Carcasa_v4 (Autodesk Fusion 360 design; units mm, degrees)
part number: 2026-11-08-16-02-31-527
part number: 2026-11-08-16-03-12-914
part number: 2026-11-08-16-03-47-688
part number: 2026-11-08-16-03-50-916
part number: 2026-11-08-16-04-46-221
part number: 2026-11-08-16-04-50-854
part number: 2026-11-08-17-01-50-922
part number: 2026-11-08-17-01-54-591
part number: 2026-11-15-20-32-03-363
Autodesk Fusion 360 part; units mm, degrees
(part 1 of 2)
sketch "Boceto1" plane through (0, 0, 0) normal (0, 0, 1) x (1, 0, 0) in component "Cuerpo"
  line L0 (-55, -5) -> (55, -5)
  line L1 (55, -5) -> (55, 65)
  line L2 (55, 65) -> (-55, 65)
  line L3 (-55, 65) -> (-55, -5)
extrude "Extruir1" add sketch "Boceto1" along normal blind 100 makes body 1 in component "Cuerpo"
fillet "Empalme1" radius 8 4 edges at (-55, 65, 50) (55, 65, 50) (55, -5, 50) (-55, -5, 50) on bodies 1 in component "Cuerpo"
fillet "Empalme2" radius 3 128 edges at (-52.6569, -2.6569, 100) (-55, 30, 100) (-52.6569, 62.6569, 100) (0, 65, 100) (52.6569, 62.6569, 100) (55, 30, 100) (52.6569, -2.6569, 100) (0, -5, 100) (0, -5, 100) (52.6569, -2.6569, 100) (55, 30, 100) (52.6569, 62.6569, 100) (0, 65, 100) (-52.6569, 62.6569, 100) (-55, 30, 100) (-52.6569, -2.6569, 100) (52.6569, -2.6569, 100) (0, -5, 100) (-52.6569, -2.6569, 100) (-55, 30, 100) (-52.6569, 62.6569, 100) (0, 65, 100) (52.6569, 62.6569, 100) (55, 30, 100) (55, 30, 100) (52.6569, 62.6569, 100) (0, 65, 100) (-52.6569, 62.6569, 100) (-55, 30, 100) (-52.6569, -2.6569, 100) (0, -5, 100) (52.6569, -2.6569, 100) (52.6569, 62.6569, 100) (55, 30, 100) (52.6569, -2.6569, 100) (0, -5, 100) (-52.6569, -2.6569, 100) (-55, 30, 100) (-52.6569, 62.6569, 100) (0, 65, 100) (0, 65, 100) (-52.6569, 62.6569, 100) (-55, 30, 100) (-52.6569, -2.6569, 100) (0, -5, 100) (52.6569, -2.6569, 100) (55, 30, 100) (52.6569, 62.6569, 100) (-52.6569, 62.6569, 100) (0, 65, 100) (52.6569, 62.6569, 100) (55, 30, 100) (52.6569, -2.6569, 100) (0, -5, 100) (-52.6569, -2.6569, 100) (-55, 30, 100) (-55, 30, 100) (-52.6569, -2.6569, 100) (0, -5, 100) (52.6569, -2.6569, 100) (55, 30, 100) (52.6569, 62.6569, 100) (0, 65, 100) (-52.6569, 62.6569, 100) (-52.6569, -2.6569, 0) (0, -5, 0) (52.6569, -2.6569, 0) (55, 30, 0) (52.6569, 62.6569, 0) (0, 65, 0) (-52.6569, 62.6569, 0) (-55, 30, 0) (-55, 30, 0) (-52.6569, -2.6569, 0) (0, -5, 0) (52.6569, -2.6569, 0) (55, 30, 0) (52.6569, 62.6569, 0) (0, 65, 0) (-52.6569, 62.6569, 0) (-52.6569, 62.6569, 0) (-55, 30, 0) (-52.6569, -2.6569, 0) (0, -5, 0) (52.6569, -2.6569, 0) (55, 30, 0) (52.6569, 62.6569, 0) (0, 65, 0) (0, 65, 0) (-52.6569, 62.6569, 0) (-55, 30, 0) (-52.6569, -2.6569, 0) (0, -5, 0) (52.6569, -2.6569, 0) (55, 30, 0) (52.6569, 62.6569, 0) (52.6569, 62.6569, 0) (0, 65, 0) (-52.6569, 62.6569, 0) (-55, 30, 0) (-52.6569, -2.6569, 0) (0, -5, 0) (52.6569, -2.6569, 0) (55, 30, 0) (55, 30, 0) (52.6569, 62.6569, 0) (0, 65, 0) (-52.6569, 62.6569, 0) (-55, 30, 0) (-52.6569, -2.6569, 0) (0, -5, 0) (52.6569, -2.6569, 0) (52.6569, -2.6569, 0) (55, 30, 0) (52.6569, 62.6569, 0) (0, 65, 0) (-52.6569, 62.6569, 0) (-55, 30, 0) (-52.6569, -2.6569, 0) (0, -5, 0) (0, -5, 0) (52.6569, -2.6569, 0) (55, 30, 0) (52.6569, 62.6569, 0) (0, 65, 0) (-52.6569, 62.6569, 0) (-55, 30, 0) (-52.6569, -2.6569, 0) on bodies 1 in component "Cuerpo"
ref_plane "PlanoDeObra1" through (0, -3, 0) normal (0, 1, 0) x (0, 0, 1) in component "Cuerpo"
sketch "Boceto2" plane through (0, -3, 0) normal (0, 1, 0) x (1, 0, 0) in component "Cuerpo"
  line L0 (-70, 10) -> (70, 10)
  line L1 (70, 10) -> (70, -120)
  line L2 (70, -120) -> (-70, -120)
  line L3 (-70, -120) -> (-70, 10)
extrude "Extruir2" cut sketch "Boceto2" along normal mid plane 6 bodies 1 in component "Cuerpo"
shell "Vaciado1" thickness 2.5 removed faces 1 at (17, 0, 66.6667) on bodies 1 in component "Cuerpo"
sketch "Boceto3" plane through (0, 0, 0) normal (0, 1, 0) x (1, 0, 0) in component "Cuerpo"
  circle A0 centre (-48.8, -12) radius 4
  circle A1 centre (-48.8, -88) radius 4
  circle A2 centre (48.8, -12) radius 4
  circle A3 centre (48.8, -88) radius 4
extrude "Extruir3" add sketch "Boceto3" along normal blind 12 bodies 1 in component "Cuerpo"
ref_plane "PlanoDeObra2" through (0, 0, 2) normal (0, 0, 1) x (1, 0, 0) in component "Cuerpo"
ref_plane "PlanoDeObra3" through (0, 0, 2) normal (0, 0, 1) x (1, 0, 0) in component "Cuerpo"
ref_plane "PlanoDeObra4" through (0, 0, 8) normal (0, 0, 1) x (1, 0, 0) in component "Cuerpo"
ref_plane "PlanoDeObra5" through (0, 21, 0) normal (0, 1, 0) x (0, 0, 1) in component "Cuerpo"
ref_plane "PlanoDeObra6" through (0, 21, 0) normal (0, 1, 0) x (0, 0, 1) in component "Cuerpo"
ref_plane "PlanoDeObra7" through (0, 0, 5) normal (0, 0, 1) x (1, 0, 0) in component "Cuerpo"
sketch "Boceto10" plane through (0, 0, 5) normal (0, 0, 1) x (1, 0, 0) in component "Cuerpo"
  line L0 (-20, 64) -> (20, 64)
  line L1 (20, 64) -> (20, 73)
  line L2 (20, 73) -> (-20, 73)
  line L3 (-20, 73) -> (-20, 64)
extrude "Extruir10" add sketch "Boceto10" along normal blind 90 bodies 1 in component "Cuerpo"
ref_plane "PlanoDeObra8" through (0, 0, 4) normal (0, 0, 1) x (1, 0, 0) in component "Cuerpo"
sketch "Boceto11" plane through (0, 0, 4) normal (0, 0, 1) x (1, 0, 0) in component "Cuerpo"
  line L0 (-10.3, 74) -> (10.3, 74)
  line L1 (10.3, 74) -> (14, 67)
  line L2 (14, 67) -> (-14, 67)
  line L3 (-14, 67) -> (-10.3, 74)
extrude "Extruir11" cut sketch "Boceto11" along normal blind 81 bodies 1 in component "Cuerpo"
sketch "Boceto12" plane through (0, 0, 0) normal (1, 0, 0) x (0, 0, -1) in component "Cuerpo"
  circle A0 centre (-75, 70) radius 2
extrude "Extruir12" cut sketch "Boceto12" along normal mid plane 50 bodies 1 in component "Cuerpo"
sketch "Boceto13" plane through (0, 0, 0) normal (0, 0, 1) x (1, 0, 0) in component "Cuerpo"
  circle A0 centre (-25, 30) radius 1.5
  circle A1 centre (25, 30) radius 1.5
extrude "Extruir13" cut sketch "Boceto13" along normal blind 4 bodies 1 in component "Cuerpo"
ref_plane "PlanoDeObra9" through (0, 0, 96) normal (0, 0, 1) x (1, 0, 0) in component "Cuerpo"
ref_plane "PlanoDeObra10" through (0, 0, 100) normal (0, 0, 1) x (1, 0, 0) in component "Cuerpo"
ref_plane "PlanoDeObra1" through (0, -3.5, 0) normal (0, 1, 0) x (0, 0, 1) in component "Tapa frontal"
sketch "Boceto1 (2)" plane through (0, -3.5, 0) normal (0, 1, 0) x (1, 0, 0) in component "Tapa frontal"
  line L0 (-54.4, 0) -> (54.4, 0)
  line L1 (54.4, 0) -> (54.4, -100)
  line L2 (54.4, -100) -> (-54.4, -100)
  line L3 (-54.4, -100) -> (-54.4, 0)
extrude "Extruir1'" add sketch "Boceto1 (2)" along normal mid plane 3 separate body makes body 2 in component "Tapa frontal"
fillet "Empalme1'" radius 3 4 edges at (-54.4, -3.5, 100) (-54.4, -3.5, 0) (54.4, -3.5, 0) (54.4, -3.5, 100) on bodies 2 in component "Tapa frontal"
fillet "Empalme2'" radius 1.5 64 edges at (53.5213, -5, 99.1213) (54.4, -5, 50) (53.5213, -5, 0.8787) (0, -5, 0) (-53.5213, -5, 0.8787) (-54.4, -5, 50) (-53.5213, -5, 99.1213) (0, -5, 100) (54.4, -5, 50) (53.5213, -5, 99.1213) (0, -5, 100) (-53.5213, -5, 99.1213) (-54.4, -5, 50) (-53.5213, -5, 0.8787) (0, -5, 0) (53.5213, -5, 0.8787) (0, -5, 100) (-53.5213, -5, 99.1213) (-54.4, -5, 50) (-53.5213, -5, 0.8787) (0, -5, 0) (53.5213, -5, 0.8787) (54.4, -5, 50) (53.5213, -5, 99.1213) (-53.5213, -5, 99.1213) (0, -5, 100) (53.5213, -5, 99.1213) (54.4, -5, 50) (53.5213, -5, 0.8787) (0, -5, 0) (-53.5213, -5, 0.8787) (-54.4, -5, 50) (-54.4, -5, 50) (-53.5213, -5, 0.8787) (0, -5, 0) (53.5213, -5, 0.8787) (54.4, -5, 50) (53.5213, -5, 99.1213) (0, -5, 100) (-53.5213, -5, 99.1213) (-53.5213, -5, 0.8787) (-54.4, -5, 50) (-53.5213, -5, 99.1213) (0, -5, 100) (53.5213, -5, 99.1213) (54.4, -5, 50) (53.5213, -5, 0.8787) (0, -5, 0) (0, -5, 0) (53.5213, -5, 0.8787) (54.4, -5, 50) (53.5213, -5, 99.1213) (0, -5, 100) (-53.5213, -5, 99.1213) (-54.4, -5, 50) (-53.5213, -5, 0.8787) (53.5213, -5, 0.8787) (0, -5, 0) (-53.5213, -5, 0.8787) (-54.4, -5, 50) (-53.5213, -5, 99.1213) (0, -5, 100) (53.5213, -5, 99.1213) (54.4, -5, 50) on bodies 2 in component "Tapa frontal"
ref_plane "PlanoDeObra2" through (0, 1.5, 0) normal (0, 1, 0) x (0, 0, 1) in component "Tapa frontal"
sketch "Boceto2 (2)" plane through (0, 1.5, 0) normal (0, 1, 0) x (1, 0, 0) in component "Tapa frontal"
  line L0 (-51.6, -2.8) -> (51.6, -2.8)
  line L1 (51.6, -2.8) -> (51.6, -97.2)
  line L2 (51.6, -97.2) -> (-51.6, -97.2)
  line L3 (-51.6, -97.2) -> (-51.6, -2.8)
  line L4 (-50, -4.4) -> (50, -4.4)
  line L5 (50, -4.4) -> (50, -95.6)
  line L6 (50, -95.6) -> (-50, -95.6)
  line L7 (-50, -95.6) -> (-50, -4.4)
extrude "Extruir2'" add sketch "Boceto2 (2)" along normal mid plane 7 bodies 2 in component "Tapa frontal"
ref_plane "PlanoDeObra3" through (0, 1.5, 0) normal (0, 1, 0) x (0, 0, 1) in component "Tapa frontal"
sketch "Boceto3 (2)" plane through (0, 1.5, 0) normal (0, 1, 0) x (1, 0, 0) in component "Tapa frontal"
  line L0 (-53.8, -7) -> (-43.8, -7)
  line L1 (-43.8, -7) -> (-43.8, -17)
  line L2 (-43.8, -17) -> (-53.8, -17)
  line L3 (-53.8, -17) -> (-53.8, -7)
  line L4 (-53.8, -83) -> (-43.8, -83)
  line L5 (-43.8, -83) -> (-43.8, -93)
  line L6 (-43.8, -93) -> (-53.8, -93)
  line L7 (-53.8, -93) -> (-53.8, -83)
  line L8 (43.8, -7) -> (53.8, -7)
  line L9 (53.8, -7) -> (53.8, -17)
  line L10 (53.8, -17) -> (43.8, -17)
  line L11 (43.8, -17) -> (43.8, -7)
  line L12 (43.8, -83) -> (53.8, -83)
  line L13 (53.8, -83) -> (53.8, -93)
  line L14 (53.8, -93) -> (43.8, -93)
  line L15 (43.8, -93) -> (43.8, -83)
extrude "Extruir3'" cut sketch "Boceto3 (2)" along normal mid plane 7 bodies 2 in component "Tapa frontal"
ref_plane "PlanoDeObra4" through (0, -1.25, 0) normal (0, 1, 0) x (0, 0, 1) in component "Tapa frontal"
sketch "Boceto4" plane through (0, -1.25, 0) normal (0, 1, 0) x (1, 0, 0) in component "Tapa frontal"
  circle A0 centre (-48.8, -12) radius 4
  circle A1 centre (-48.8, -88) radius 4
  circle A2 centre (48.8, -12) radius 4
  circle A3 centre (48.8, -88) radius 4
extrude "Extruir4" add sketch "Boceto4" along normal mid plane 1.5 bodies 2 in component "Tapa frontal"
ref_plane "PlanoDeObra5" through (0, -3.5, 0) normal (0, 1, 0) x (0, 0, 1) in component "Tapa frontal"
sketch "Boceto5" plane through (0, -3.5, 0) normal (0, 1, 0) x (1, 0, 0) in component "Tapa frontal"
  circle A0 centre (-48.8, -12) radius 1.7
  circle A1 centre (-48.8, -88) radius 1.7
  circle A2 centre (48.8, -12) radius 1.7
  circle A3 centre (48.8, -88) radius 1.7
extrude "Extruir5" cut sketch "Boceto5" along normal mid plane 10 bodies 2 in component "Tapa frontal"
ref_plane "PlanoDeObra6" through (0, -5, 0) normal (0, 1, 0) x (0, 0, 1) in component "Tapa frontal"
sketch "Boceto6" plane through (0, -5, 0) normal (0, 1, 0) x (1, 0, 0) in component "Tapa frontal"
  circle A0 centre (-48.8, -12) radius 3.25
  circle A1 centre (-48.8, -88) radius 3.25
  circle A2 centre (48.8, -12) radius 3.25
  circle A3 centre (48.8, -88) radius 3.25
extrude "Extruir6" cut sketch "Boceto6" along normal blind 1.5 bodies 2 in component "Tapa frontal"
ref_plane "PlanoDeObra7" through (0, 2.25, 0) normal (0, 1, 0) x (0, 0, 1) in component "Tapa frontal"
ref_plane "PlanoDeObra8" through (0, 2.25, 0) normal (0, 1, 0) x (0, 0, 1) in component "Tapa frontal"
ref_plane "PlanoDeObra9" through (0, -5.75, 0) normal (0, 1, 0) x (0, 0, 1) in component "Tapa frontal"
sketch "Boceto9" plane through (0, -5.75, 0) normal (0, 1, 0) x (1, 0, 0) in component "Tapa frontal"
  line L0 (-12, -52) -> (12, -52)
  line L1 (12, -52) -> (12, -95)
  line L2 (12, -95) -> (-12, -95)
  line L3 (-12, -95) -> (-12, -52)
extrude "Extruir9" add sketch "Boceto9" along normal mid plane 1.5 separate body makes body 3 in component "Tapa frontal"
fillet "Empalme3" radius 3 4 edges at (-12, -5.75, 95) (-12, -5.75, 52) (12, -5.75, 52) (12, -5.75, 95) on bodies 3 in component "Tapa frontal"
ref_plane "PlanoDeObra10" through (0, -12.45, 0) normal (0, 1, 0) x (0, 0, 1) in component "Tapa frontal"
sketch "Boceto10 (2)" plane through (0, -12.45, 0) normal (0, 1, 0) x (1, 0, 0) in component "Tapa frontal"
  arc A0 (-6.5, -60.4) -> (6.5, -60.4) centre (0, -60.4) ccw
  arc A1 (-5, -60.4) -> (5, -60.4) centre (0, -60.4) ccw
  line L0 (6.5, -60.4) -> (5, -60.4)
  line L1 (-6.5, -60.4) -> (-5, -60.4)
  arc A2 (-6.5, -72.4) -> (6.5, -72.4) centre (0, -72.4) ccw
  arc A3 (-5, -72.4) -> (5, -72.4) centre (0, -72.4) ccw
  line L2 (6.5, -72.4) -> (5, -72.4)
  line L3 (-6.5, -72.4) -> (-5, -72.4)
  arc A4 (-6.5, -84.3) -> (6.5, -84.3) centre (0, -84.3) ccw
  arc A5 (-5, -84.3) -> (5, -84.3) centre (0, -84.3) ccw
  line L4 (6.5, -84.3) -> (5, -84.3)
  line L5 (-6.5, -84.3) -> (-5, -84.3)
extrude "Extruir10'" add sketch "Boceto10 (2)" along normal mid plane 12.1 bodies 3 in component "Tapa frontal"
ref_plane "PlanoDeObra11" through (0, -3.5, 0) normal (0, 1, 0) x (0, 0, 1) in component "Tapa frontal"
sketch "Boceto11 (2)" plane through (0, -3.5, 0) normal (0, 1, 0) x (1, 0, 0) in component "Tapa frontal"
  circle A0 centre (0, -60.4) radius 3.8
  circle A1 centre (0, -72.4) radius 3.8
  circle A2 centre (0, -84.3) radius 3.8
extrude "Extruir11'" cut sketch "Boceto11 (2)" along normal mid plane 10 bodies 2 3 in component "Tapa frontal"
ref_plane "PlanoDeObra12" through (0, -3.5, 0) normal (0, 1, 0) x (0, 0, 1) in component "Tapa frontal"
ref_plane "PlanoDeObra1" through (0, -1, 0) normal (0, 1, 0) x (0, 0, 1) in component "Junta TPU"
sketch "Boceto1 (3)" plane through (0, -1, 0) normal (0, 1, 0) x (1, 0, 0) in component "Junta TPU"
  line L0 (-54.4, 0) -> (54.4, 0)
  line L1 (54.4, 0) -> (54.4, -100)
  line L2 (54.4, -100) -> (-54.4, -100)
  line L3 (-54.4, -100) -> (-54.4, 0)
  line L4 (-51.9, -2.5) -> (51.9, -2.5)
  line L5 (51.9, -2.5) -> (51.9, -97.5)
  line L6 (51.9, -97.5) -> (-51.9, -97.5)
  line L7 (-51.9, -97.5) -> (-51.9, -2.5)
extrude "Extruir1''" add sketch "Boceto1 (3)" along normal mid plane 2 separate body makes body 4 in component "Junta TPU"
fillet "Empalme1''" radius 3 4 edges at (-54.4, -1, 100) (-54.4, -1, 0) (54.4, -1, 0) (54.4, -1, 100) on bodies 4 in component "Junta TPU"
ref_plane "PlanoDeObra2" through (0, -1, 0) normal (0, 1, 0) x (0, 0, 1) in component "Junta TPU"
sketch "Boceto2 (3)" plane through (0, -1, 0) normal (0, 1, 0) x (1, 0, 0) in component "Junta TPU"
  circle A0 centre (-48.8, -12) radius 4.3
  circle A1 centre (-48.8, -88) radius 4.3
  circle A2 centre (48.8, -12) radius 4.3
  circle A3 centre (48.8, -88) radius 4.3
extrude "Extruir2''" cut sketch "Boceto2 (3)" along normal mid plane 3 bodies 4 in component "Junta TPU"
sketch "Boceto1 (4)" plane through (0, 0, 0) normal (0, 0, 1) x (1, 0, 0) in component "Techo solar"
  point P0 (-57.5, -24)
  point P1 (57.5, -24)
  point P2 (0, 82.1853)
ref_plane "PlanoDeObra1" through (-57.5, -24, 104) normal (0, -0.34202, 0.939693) x (1, 0, 0) in component "Techo solar"
ref_plane "PlanoDeObra2" through (-57.5, -25.3681, 107.7588) normal (0, -0.34202, 0.939693) x (1, 0, 0) in component "Techo solar"
sketch "Boceto2 (4)" plane through (0, -36.2324, 99.5478) normal (0, -0.34202, 0.939693) x (1, 0, 0) in component "Techo solar"
  line L0 (-57.5, 13.0175) -> (57.5, 13.0175)
  line L1 (57.5, 13.0175) -> (57.5, 126.0175)
  line L2 (57.5, 126.0175) -> (-57.5, 126.0175)
  line L3 (-57.5, 126.0175) -> (-57.5, 13.0175)
extrude "Extruir1'''" add sketch "Boceto2 (4)" along normal blind 4 separate body makes body 5 in component "Techo solar"
ref_plane "PlanoDeObra3" through (0, 0, 118) normal (0, 0, 1) x (1, 0, 0) in component "Techo solar"
sketch "Boceto3 (3)" plane through (0, 0, 118) normal (0, 0, 1) x (1, 0, 0) in component "Techo solar"
  line L0 (28, 22) -> (56, 22)
  line L1 (56, 22) -> (56, 80)
  line L2 (56, 80) -> (28, 80)
  line L3 (28, 80) -> (28, 22)
extrude "Extruir2'''" add sketch "Boceto3 (3)" along normal blind 32 bodies 5 in component "Techo solar"
fillet "Empalme1'''" radius 3 8 edges at (28, 22, 119.3713) (56, 22, 119.3713) (28, 80, 129.9265) (56, 80, 129.9265) (56, 80, 148.0548) (56, 22, 137.4997) (28, 80, 148.0548) (28, 22, 137.4997) on bodies 5 in component "Techo solar"
sketch "Boceto4 (2)" plane through (0, -36.2324, 99.5478) normal (0, -0.34202, 0.939693) x (1, 0, 0) in component "Techo solar"
  line L0 (26, 53.0175) -> (58, 53.0175)
  line L1 (58, 53.0175) -> (58, 131.0175)
  line L2 (58, 131.0175) -> (26, 131.0175)
  line L3 (26, 131.0175) -> (26, 53.0175)
extrude "Extruir3''" cut sketch "Boceto4 (2)" against normal blind 40 bodies 5 in component "Techo solar"
ref_plane "PlanoDeObra4" through (0, 0, 100) normal (0, 0, 1) x (1, 0, 0) in component "Techo solar"
ref_plane "PlanoDeObra5" through (0, 0, 100) normal (0, 0, 1) x (1, 0, 0) in component "Techo solar"
ref_plane "PlanoDeObra6" through (0, 0, 100) normal (0, 0, 1) x (1, 0, 0) in component "Techo solar"
ref_plane "PlanoDeObra7" through (0, 0, 100) normal (0, 0, 1) x (1, 0, 0) in component "Techo solar"
ref_plane "PlanoDeObra8" through (0, 0, 100) normal (0, 0, 1) x (1, 0, 0) in component "Techo solar"
ref_plane "PlanoDeObra9" through (0, 0, 150) normal (0, 0, 1) x (1, 0, 0) in component "Techo solar"
sketch "Boceto10 (3)" plane through (0, 0, 150) normal (0, 0, 1) x (1, 0, 0) in component "Techo solar"
  line L0 (30, 24) -> (54, 24)
  line L1 (54, 24) -> (54, 78)
  line L2 (54, 78) -> (30, 78)
  line L3 (30, 78) -> (30, 24)
extrude "Extruir9'" cut sketch "Boceto10 (3)" along normal up to surface end surface through (-57.5, -25.3681, 107.7588) normal (0, -0.34202, 0.939693) offset 0 bodies 5 in component "Techo solar"
sketch "Boceto11 (3)" plane through (0, -37.6005, 103.3065) normal (0, -0.34202, 0.939693) x (1, 0, 0) in component "Techo solar"
  line L0 (-55, 17.7175) -> (25.6, 17.7175)
  line L1 (25.6, 17.7175) -> (25.6, 118.3175)
  line L2 (25.6, 118.3175) -> (-55, 118.3175)
  line L3 (-55, 118.3175) -> (-55, 17.7175)
extrude "Extruir10''" cut sketch "Boceto11 (3)" against normal blind 2.6 bodies 5 in component "Techo solar"
sketch "Boceto12 (2)" plane through (0, -37.6005, 103.3065) normal (0, -0.34202, 0.939693) x (1, 0, 0) in component "Techo solar"
  line L0 (-48, 19.7175) -> (23.6, 19.7175)
  line L1 (23.6, 19.7175) -> (23.6, 116.3175)
  line L2 (23.6, 116.3175) -> (-48, 116.3175)
  line L3 (-48, 116.3175) -> (-48, 19.7175)
  line L4 (-55, 108.0175) -> (-48.2, 108.0175)
  line L5 (-48.2, 108.0175) -> (-48.2, 116.3175)
  line L6 (-48.2, 116.3175) -> (-55, 116.3175)
  line L7 (-55, 116.3175) -> (-55, 108.0175)
extrude "Extruir11''" cut sketch "Boceto12 (2)" against normal blind 4.6 bodies 5 in component "Techo solar"
sketch "Boceto13 (2)" plane through (0, -37.6005, 103.3065) normal (0, -0.34202, 0.939693) x (1, 0, 0) in component "Techo solar"
  line L0 (-40, 15.7175) -> (-30, 15.7175)
  line L1 (-30, 15.7175) -> (-30, 19.3175)
  line L2 (-30, 19.3175) -> (-40, 19.3175)
  line L3 (-40, 19.3175) -> (-40, 15.7175)
  line L4 (-40, 116.7175) -> (-30, 116.7175)
  line L5 (-30, 116.7175) -> (-30, 120.3175)
  line L6 (-30, 120.3175) -> (-40, 120.3175)
  line L7 (-40, 120.3175) -> (-40, 116.7175)
  line L8 (0, 15.7175) -> (10, 15.7175)
  line L9 (10, 15.7175) -> (10, 19.3175)
  line L10 (10, 19.3175) -> (0, 19.3175)
  line L11 (0, 19.3175) -> (0, 15.7175)
  line L12 (0, 116.7175) -> (10, 116.7175)
  line L13 (10, 116.7175) -> (10, 120.3175)
  line L14 (10, 120.3175) -> (0, 120.3175)
  line L15 (0, 120.3175) -> (0, 116.7175)
extrude "Extruir12'" add sketch "Boceto13 (2)" along normal blind 1.2 bodies 5 in component "Techo solar"
ref_plane "PlanoDeObra10" through (0, 0, 122) normal (0, 0, 1) x (1, 0, 0) in component "Techo solar"
ref_plane "PlanoDeObra1" through (0, 0, 150) normal (0, 0, 1) x (1, 0, 0) in component "Tapa sensor"
sketch "Boceto1 (5)" plane through (0, 0, 150) normal (0, 0, 1) x (1, 0, 0) in component "Tapa sensor"
  line L0 (28, 22) -> (56, 22)
  line L1 (56, 22) -> (56, 80)
  line L2 (56, 80) -> (28, 80)
  line L3 (28, 80) -> (28, 22)
extrude "Extruir1''''" add sketch "Boceto1 (5)" along normal blind 3 separate body makes body 6 in component "Tapa sensor"
fillet "Empalme1''''" radius 3 4 edges at (28, 80, 151.5) (56, 80, 151.5) (56, 22, 151.5) (28, 22, 151.5) on bodies 6 in component "Tapa sensor"
ref_plane "PlanoDeObra2" through (0, 0, 150) normal (0, 0, 1) x (1, 0, 0) in component "Tapa sensor"
sketch "Boceto2 (5)" plane through (0, 0, 150) normal (0, 0, 1) x (1, 0, 0) in component "Tapa sensor"
  line L0 (30.2, 24.2) -> (53.8, 24.2)
  line L1 (53.8, 24.2) -> (53.8, 77.8)
  line L2 (53.8, 77.8) -> (30.2, 77.8)
  line L3 (30.2, 77.8) -> (30.2, 24.2)
  line L4 (31.7, 25.7) -> (52.3, 25.7)
  line L5 (52.3, 25.7) -> (52.3, 76.3)
  line L6 (52.3, 76.3) -> (31.7, 76.3)
  line L7 (31.7, 76.3) -> (31.7, 25.7)
extrude "Extruir2''''" add sketch "Boceto2 (5)" against normal blind 2.5 bodies 6 in component "Tapa sensor"
ref_plane "PlanoDeObra3" through (0, 0, 147) normal (0, 0, 1) x (1, 0, 0) in component "Tapa sensor"
sketch "Boceto3 (4)" plane through (0, 0, 147) normal (0, 0, 1) x (1, 0, 0) in component "Tapa sensor"
  line L0 (29, 74) -> (55, 74)
  line L1 (55, 74) -> (55, 79)
  line L2 (55, 79) -> (29, 79)
  line L3 (29, 79) -> (29, 74)
extrude "Extruir3'''" cut sketch "Boceto3 (4)" along normal blind 3 bodies 6 in component "Tapa sensor"
ref_plane "PlanoDeObra4" through (0, 0, 150) normal (0, 0, 1) x (1, 0, 0) in component "Tapa sensor"
ref_plane "PlanoDeObra5" through (0, 0, 151) normal (0, 0, 1) x (1, 0, 0) in component "Tapa sensor"
ref_plane "PlanoDeObra6" through (0, 0, 153) normal (0, 0, 1) x (1, 0, 0) in component "Tapa sensor"
sketch "Boceto6 (2)" plane through (0, 0, 153) normal (0, 0, 1) x (1, 0, 0) in component "Tapa sensor"
  circle A0 centre (42, 31) radius 9
  circle A1 centre (42, 31) radius 7.9
extrude "Extruir6'" add sketch "Boceto6 (2)" along normal blind 1.5 bodies 6 in component "Tapa sensor"
ref_plane "PlanoDeObra7" through (42, 0, 0) normal (1, 0, 0) x (0, 1, 0) in component "Tapa sensor"
sketch "Boceto7" plane through (42, 0, 0) normal (1, 0, 0) x (0, 0, -1) in component "Tapa sensor"
  line L0 (-149.5, 31) -> (-149.5, 33.5)
  line L1 (-149.5, 33.5) -> (-150, 33.5)
  line L2 (-150, 33.5) -> (-153, 38.7)
  line L3 (-153, 38.7) -> (-153.6, 38.7)
  line L4 (-153.6, 38.7) -> (-153.6, 31)
  line L5 (-153.6, 31) -> (-149.5, 31)
revolve "Revolución1" cut sketch "Boceto7" angle 360 about axis through (42, 31, 153.6) along (0, 0, -1) bodies 6 in component "Tapa sensor"
ref_plane "PlanoDeObra11" through (0, 0, 122) normal (0, 0, 1) x (1, 0, 0) in component "Techo solar"
sketch "Boceto1 (6)" plane through (0, 0, 0) normal (0, 0, 1) x (1, 0, 0) in component "Soporte pared"
  line L0 (-35, 73.3) -> (35, 73.3)
  line L1 (35, 73.3) -> (35, 86)
  line L2 (35, 86) -> (-35, 86)
  line L3 (-35, 86) -> (-35, 73.3)
extrude "Extruir1'''''" add sketch "Boceto1 (6)" along normal blind 95 separate body makes body 7 in component "Soporte pared"
fillet "Empalme1'''''" radius 5 4 edges at (35, 79.65, 0) (35, 79.65, 95) (-35, 79.65, 0) (-35, 79.65, 95) on bodies 7 in component "Soporte pared"
ref_plane "PlanoDeObra1" through (0, 0, 8) normal (0, 0, 1) x (1, 0, 0) in component "Soporte pared"
sketch "Boceto2 (6)" plane through (0, 0, 8) normal (0, 0, 1) x (1, 0, 0) in component "Soporte pared"
  line L0 (-13.54, 67.3) -> (13.54, 67.3)
  line L1 (13.54, 67.3) -> (10.21, 73.6)
  line L2 (10.21, 73.6) -> (-10.21, 73.6)
  line L3 (-10.21, 73.6) -> (-13.54, 67.3)
extrude "Extruir2'''''" add sketch "Boceto2 (6)" along normal blind 76.7 bodies 7 in component "Soporte pared"
ref_plane "PlanoDeObra2" through (0, 82.15, 0) normal (0, 1, 0) x (0, 0, 1) in component "Soporte pared"
sketch "Boceto3 (5)" plane through (0, 82.15, 0) normal (0, 1, 0) x (1, 0, 0) in component "Soporte pared"
  line L0 (-29, -8) -> (29, -8)
  line L1 (29, -8) -> (29, -87)
  line L2 (29, -87) -> (-29, -87)
  line L3 (-29, -87) -> (-29, -8)
extrude "Extruir3''''" cut sketch "Boceto3 (5)" along normal mid plane 7.8 bodies 7 in component "Soporte pared"
ref_plane "PlanoDeObra3" through (0, 80, 0) normal (0, 1, 0) x (0, 0, 1) in component "Soporte pared"
sketch "Boceto4 (3)" plane through (0, 80, 0) normal (0, 1, 0) x (1, 0, 0) in component "Soporte pared"
  circle A0 centre (-26, -14) radius 2.5
  circle A1 centre (-26, -81) radius 2.5
  circle A2 centre (26, -14) radius 2.5
  circle A3 centre (26, -81) radius 2.5
extrude "Extruir4'" cut sketch "Boceto4 (3)" along normal mid plane 20 bodies 7 in component "Soporte pared"
ref_plane "PlanoDeObra4" through (0, 73.3, 0) normal (0, 1, 0) x (0, 0, 1) in component "Soporte pared"
sketch "Boceto5 (2)" plane through (0, 73.3, 0) normal (0, 1, 0) x (1, 0, 0) in component "Soporte pared"
  circle A0 centre (-26, -14) radius 4.5
  circle A1 centre (-26, -81) radius 4.5
  circle A2 centre (26, -14) radius 4.5
  circle A3 centre (26, -81) radius 4.5
extrude "Extruir5'" cut sketch "Boceto5 (2)" along normal blind 2.5 bodies 7 in component "Soporte pared"
sketch "Boceto6 (3)" plane through (0, 0, 0) normal (1, 0, 0) x (0, 0, -1) in component "Soporte pared"
  circle A0 centre (-75, 70) radius 2
extrude "Extruir6''" cut sketch "Boceto6 (3)" along normal mid plane 60 bodies 7 in component "Soporte pared"
ref_plane "PlanoDeObra1" through (0, 96, 0) normal (0, 1, 0) x (0, 0, 1) in component "Pared (referencia)"
sketch "Boceto1 (7)" plane through (0, 96, 0) normal (0, 1, 0) x (1, 0, 0) in component "Pared (referencia)"
  line L0 (-120, 80) -> (120, 80)
  line L1 (120, 80) -> (120, -240)
  line L2 (120, -240) -> (-120, -240)
  line L3 (-120, -240) -> (-120, 80)
extrude "Extruir1''''''" add sketch "Boceto1 (7)" along normal mid plane 20 separate body makes body 8 in component "Pared (referencia)"
ref_plane "PlanoDeObra1" through (0, 54, 0) normal (0, 1, 0) x (0, 0, 1) in component "Traba bateria"
sketch "Boceto1 (8)" plane through (0, 54, 0) normal (0, 1, 0) x (1, 0, 0) in component "Traba bateria"
  line L0 (-22.5, -45.5) -> (-15.5, -45.5)
  line L1 (-15.5, -45.5) -> (-15.5, -96.5)
  line L2 (-15.5, -96.5) -> (-22.5, -96.5)
  line L3 (-22.5, -96.5) -> (-22.5, -45.5)
extrude "Traba bateria (1)" add sketch "Boceto1 (8)" along normal blind 2 separate body makes body 9 in component "Traba bateria"
ref_plane "PlanoDeObra2" through (0, 53, 0) normal (0, 1, 0) x (0, 0, 1) in component "Traba bateria"
sketch "Boceto2 (7)" plane through (0, 53, 0) normal (0, 1, 0) x (1, 0, 0) in component "Traba bateria"
  circle A0 centre (-19, -49.5) radius 1.7
  circle A1 centre (-19, -92.5) radius 1.7
extrude "Agujeros traba M3 (1)" cut sketch "Boceto2 (7)" along normal blind 4 bodies 9 in component "Traba bateria"
ref_plane "PlanoDeObra11" through (0, 0, 0) normal (0, 1, 0) x (0, 0, 1) in component "Cuerpo"
sketch "Boceto16" plane through (0, 0, 0) normal (0, 1, 0) x (1, 0, 0) in component "Cuerpo"
  circle A0 centre (-48.8, -12) radius 4.5
  circle A1 centre (-48.8, -88) radius 4.5
  circle A2 centre (48.8, -12) radius 4.5
  circle A3 centre (48.8, -88) radius 4.5
extrude "Torretas tapa d9 (1)" add sketch "Boceto16" along normal blind 12 bodies 1 in component "Cuerpo"
ref_plane "PlanoDeObra12" through (0, 0, 0) normal (0, 1, 0) x (0, 0, 1) in component "Cuerpo"
sketch "Boceto17" plane through (0, 0, 0) normal (0, 1, 0) x (1, 0, 0) in component "Cuerpo"
  circle A0 centre (-48.8, -12) radius 2.5
  circle A1 centre (-48.8, -88) radius 2.5
  circle A2 centre (48.8, -12) radius 2.5
  circle A3 centre (48.8, -88) radius 2.5
extrude "Insertos tapa (inserto 5x4) (1)" cut sketch "Boceto17" along normal blind 5 bodies 1 in component "Cuerpo"
ref_plane "PlanoDeObra13" through (0, 5, 0) normal (0, 1, 0) x (0, 0, 1) in component "Cuerpo"
sketch "Boceto18" plane through (0, 5, 0) normal (0, 1, 0) x (1, 0, 0) in component "Cuerpo"
  circle A0 centre (-48.8, -12) radius 1.6
  circle A1 centre (-48.8, -88) radius 1.6
  circle A2 centre (48.8, -12) radius 1.6
  circle A3 centre (48.8, -88) radius 1.6
extrude "Insertos tapa (paso M3) (1)" cut sketch "Boceto18" along normal blind 4 bodies 1 in component "Cuerpo"
ref_plane "PlanoDeObra14" through (0, 6, 0) normal (0, 1, 0) x (0, 0, 1) in component "Cuerpo"
sketch "Boceto19" plane through (0, 6, 0) normal (0, 1, 0) x (1, 0, 0) in component "Cuerpo"
  line L0 (54.5, -20) -> (60, -14.5)
  line L1 (60, -14.5) -> (60, -16)
  line L2 (60, -16) -> (54.5, -21.5)
  line L3 (54.5, -21.5) -> (54.5, -20)
  line L4 (-54.5, -20) -> (-60, -14.5)
  line L5 (-60, -14.5) -> (-60, -16)
  line L6 (-60, -16) -> (-54.5, -21.5)
  line L7 (-54.5, -21.5) -> (-54.5, -20)
  line L8 (54.5, -27) -> (60, -21.5)
  line L9 (60, -21.5) -> (60, -23)
  line L10 (60, -23) -> (54.5, -28.5)
  line L11 (54.5, -28.5) -> (54.5, -27)
  line L12 (-54.5, -27) -> (-60, -21.5)
  line L13 (-60, -21.5) -> (-60, -23)
  line L14 (-60, -23) -> (-54.5, -28.5)
  line L15 (-54.5, -28.5) -> (-54.5, -27)
  line L16 (54.5, -34) -> (60, -28.5)
  line L17 (60, -28.5) -> (60, -30)
  line L18 (60, -30) -> (54.5, -35.5)
  line L19 (54.5, -35.5) -> (54.5, -34)
  line L20 (-54.5, -34) -> (-60, -28.5)
  line L21 (-60, -28.5) -> (-60, -30)
  line L22 (-60, -30) -> (-54.5, -35.5)
  line L23 (-54.5, -35.5) -> (-54.5, -34)
  line L24 (54.5, -62) -> (60, -56.5)
  line L25 (60, -56.5) -> (60, -58)
  line L26 (60, -58) -> (54.5, -63.5)
  line L27 (54.5, -63.5) -> (54.5, -62)
  line L28 (-54.5, -62) -> (-60, -56.5)
  line L29 (-60, -56.5) -> (-60, -58)
  line L30 (-60, -58) -> (-54.5, -63.5)
  line L31 (-54.5, -63.5) -> (-54.5, -62)
  line L32 (54.5, -69) -> (60, -63.5)
  line L33 (60, -63.5) -> (60, -65)
  line L34 (60, -65) -> (54.5, -70.5)
  line L35 (54.5, -70.5) -> (54.5, -69)
  line L36 (-54.5, -69) -> (-60, -63.5)
  line L37 (-60, -63.5) -> (-60, -65)
  line L38 (-60, -65) -> (-54.5, -70.5)
  line L39 (-54.5, -70.5) -> (-54.5, -69)
  line L40 (54.5, -76) -> (60, -70.5)
  line L41 (60, -70.5) -> (60, -72)
  line L42 (60, -72) -> (54.5, -77.5)
  line L43 (54.5, -77.5) -> (54.5, -76)
  line L44 (-54.5, -76) -> (-60, -70.5)
  line L45 (-60, -70.5) -> (-60, -72)
  line L46 (-60, -72) -> (-54.5, -77.5)
  line L47 (-54.5, -77.5) -> (-54.5, -76)
extrude "Aletas persiana 45 (1)" add sketch "Boceto19" along normal blind 30 bodies 1 in component "Cuerpo"
ref_plane "PlanoDeObra15" through (0, 6, 0) normal (0, 1, 0) x (0, 0, 1) in component "Cuerpo"
sketch "Boceto20" plane through (0, 6, 0) normal (0, 1, 0) x (1, 0, 0) in component "Cuerpo"
  line L0 (51.5, -23) -> (56.5, -18)
  line L1 (56.5, -18) -> (56.5, -14)
  line L2 (56.5, -14) -> (51.5, -19)
  line L3 (51.5, -19) -> (51.5, -23)
  line L4 (-51.5, -23) -> (-56.5, -18)
  line L5 (-56.5, -18) -> (-56.5, -14)
  line L6 (-56.5, -14) -> (-51.5, -19)
  line L7 (-51.5, -19) -> (-51.5, -23)
  line L8 (51.5, -30) -> (56.5, -25)
  line L9 (56.5, -25) -> (56.5, -21)
  line L10 (56.5, -21) -> (51.5, -26)
  line L11 (51.5, -26) -> (51.5, -30)
  line L12 (-51.5, -30) -> (-56.5, -25)
  line L13 (-56.5, -25) -> (-56.5, -21)
  line L14 (-56.5, -21) -> (-51.5, -26)
  line L15 (-51.5, -26) -> (-51.5, -30)
  line L16 (51.5, -37) -> (56.5, -32)
  line L17 (56.5, -32) -> (56.5, -28)
  line L18 (56.5, -28) -> (51.5, -33)
  line L19 (51.5, -33) -> (51.5, -37)
  line L20 (-51.5, -37) -> (-56.5, -32)
  line L21 (-56.5, -32) -> (-56.5, -28)
  line L22 (-56.5, -28) -> (-51.5, -33)
  line L23 (-51.5, -33) -> (-51.5, -37)
  line L24 (51.5, -65) -> (56.5, -60)
  line L25 (56.5, -60) -> (56.5, -56)
  line L26 (56.5, -56) -> (51.5, -61)
  line L27 (51.5, -61) -> (51.5, -65)
  line L28 (-51.5, -65) -> (-56.5, -60)
  line L29 (-56.5, -60) -> (-56.5, -56)
  line L30 (-56.5, -56) -> (-51.5, -61)
  line L31 (-51.5, -61) -> (-51.5, -65)
  line L32 (51.5, -72) -> (56.5, -67)
  line L33 (56.5, -67) -> (56.5, -63)
  line L34 (56.5, -63) -> (51.5, -68)
  line L35 (51.5, -68) -> (51.5, -72)
  line L36 (-51.5, -72) -> (-56.5, -67)
  line L37 (-56.5, -67) -> (-56.5, -63)
  line L38 (-56.5, -63) -> (-51.5, -68)
  line L39 (-51.5, -68) -> (-51.5, -72)
  line L40 (51.5, -79) -> (56.5, -74)
  line L41 (56.5, -74) -> (56.5, -70)
  line L42 (56.5, -70) -> (51.5, -75)
  line L43 (51.5, -75) -> (51.5, -79)
  line L44 (-51.5, -79) -> (-56.5, -74)
  line L45 (-56.5, -74) -> (-56.5, -70)
  line L46 (-56.5, -70) -> (-51.5, -75)
  line L47 (-51.5, -75) -> (-51.5, -79)
extrude "Canales persiana 45 (1)" cut sketch "Boceto20" along normal blind 30 bodies 1 in component "Cuerpo"
ref_plane "PlanoDeObra16" through (0, 0, 96) normal (0, 0, 1) x (1, 0, 0) in component "Cuerpo"
sketch "Boceto21" plane through (0, 0, 96) normal (0, 0, 1) x (1, 0, 0) in component "Cuerpo"
  circle A0 centre (-45, 18) radius 2
  circle A1 centre (45, 18) radius 2
  circle A2 centre (-45, 52) radius 2
  circle A3 centre (45, 52) radius 2
extrude "Pasos M3 techo (1)" cut sketch "Boceto21" along normal blind 5 bodies 1 in component "Cuerpo"
ref_plane "PlanoDeObra17" through (0, 0, 100) normal (0, 0, 1) x (1, 0, 0) in component "Cuerpo"
sketch "Boceto22" plane through (0, 0, 100) normal (0, 0, 1) x (1, 0, 0) in component "Cuerpo"
  circle A0 centre (-39, 42) radius 6
  circle A1 centre (-39, 42) radius 3.5
extrude "Collarin cable panel (1)" add sketch "Boceto22" along normal blind 4 bodies 1 in component "Cuerpo"
ref_plane "PlanoDeObra18" through (0, 0, 96) normal (0, 0, 1) x (1, 0, 0) in component "Cuerpo"
sketch "Boceto23" plane through (0, 0, 96) normal (0, 0, 1) x (1, 0, 0) in component "Cuerpo"
  circle A0 centre (-39, 42) radius 3.5
extrude "Paso cable panel (1)" cut sketch "Boceto23" along normal blind 9 bodies 1 in component "Cuerpo"
ref_plane "PlanoDeObra19" through (0, 0, 100) normal (0, 0, 1) x (1, 0, 0) in component "Cuerpo"
sketch "Boceto24" plane through (0, 0, 100) normal (0, 0, 1) x (1, 0, 0) in component "Cuerpo"
  line L0 (39.3, 30.3) -> (44.7, 30.3)
  line L1 (44.7, 30.3) -> (44.7, 43.7)
  line L2 (44.7, 43.7) -> (39.3, 43.7)
  line L3 (39.3, 43.7) -> (39.3, 30.3)
  line L4 (40.5, 31.5) -> (43.5, 31.5)
  line L5 (43.5, 31.5) -> (43.5, 42.5)
  line L6 (43.5, 42.5) -> (40.5, 42.5)
  line L7 (40.5, 42.5) -> (40.5, 31.5)
extrude "Collarin cables sensor (1)" add sketch "Boceto24" along normal blind 3 bodies 1 in component "Cuerpo"
ref_plane "PlanoDeObra20" through (0, 0, 96) normal (0, 0, 1) x (1, 0, 0) in component "Cuerpo"
sketch "Boceto25" plane through (0, 0, 96) normal (0, 0, 1) x (1, 0, 0) in component "Cuerpo"
  line L0 (40.5, 31.5) -> (43.5, 31.5)
  line L1 (43.5, 31.5) -> (43.5, 42.5)
  line L2 (43.5, 42.5) -> (40.5, 42.5)
  line L3 (40.5, 42.5) -> (40.5, 31.5)
extrude "Paso cables sensor (1)" cut sketch "Boceto25" along normal blind 8 bodies 1 in component "Cuerpo"
ref_plane "PlanoDeObra21" through (0, 63, 0) normal (0, 1, 0) x (0, 0, 1) in component "Cuerpo"
sketch "Boceto26" plane through (0, 63, 0) normal (0, 1, 0) x (1, 0, 0) in component "Cuerpo"
  circle A0 centre (-31, -48.7) radius 4
  circle A1 centre (32, -48.7) radius 4
  circle A2 centre (-31, -93.3) radius 4
  circle A3 centre (32, -93.3) radius 4
extrude "Postes LiPo Rider d8 (1)" add sketch "Boceto26" against normal blind 26.1 bodies 1 in component "Cuerpo"
ref_plane "PlanoDeObra22" through (0, 63, 0) normal (0, 1, 0) x (0, 0, 1) in component "Cuerpo"
sketch "Boceto27" plane through (0, 63, 0) normal (0, 1, 0) x (1, 0, 0) in component "Cuerpo"
  circle A0 centre (-18, -10.5) radius 3.5
  circle A1 centre (33, -10.5) radius 3.5
  circle A2 centre (-18, -33.5) radius 3.5
  circle A3 centre (33, -33.5) radius 3.5
extrude "Postes ESP32 d7 (1)" add sketch "Boceto27" against normal blind 27.1 bodies 1 in component "Cuerpo"
ref_plane "PlanoDeObra23" through (0, 63, 0) normal (0, 1, 0) x (0, 0, 1) in component "Cuerpo"
ref_plane "PlanoDeObra24" through (0, 63, 0) normal (0, 1, 0) x (0, 0, 1) in component "Cuerpo"
sketch "Boceto29" plane through (0, 63, 0) normal (0, 1, 0) x (1, 0, 0) in component "Cuerpo"
  circle A0 centre (-19, -49.5) radius 4
  circle A1 centre (-19, -92.5) radius 4
extrude "Postes traba d8 (1)" add sketch "Boceto29" against normal blind 7 bodies 1 in component "Cuerpo"
ref_plane "PlanoDeObra25" through (0, 63, 0) normal (0, 1, 0) x (0, 0, 1) in component "Cuerpo"
sketch "Boceto30" plane through (0, 63, 0) normal (0, 1, 0) x (1, 0, 0) in component "Cuerpo"
  line L0 (-50, -51.5) -> (4, -51.5)
  line L1 (4, -51.5) -> (4, -90.5)
  line L2 (4, -90.5) -> (-50, -90.5)
  line L3 (-50, -90.5) -> (-50, -51.5)
  line L4 (-48.5, -53) -> (2.5, -53)
  line L5 (2.5, -53) -> (2.5, -89)
  line L6 (2.5, -89) -> (-48.5, -89)
  line L7 (-48.5, -89) -> (-48.5, -53)
extrude "Bolsillo bateria (1)" add sketch "Boceto30" against normal blind 7 bodies 1 in component "Cuerpo"
ref_plane "PlanoDeObra26" through (0, 55, 0) normal (0, 1, 0) x (0, 0, 1) in component "Cuerpo"
sketch "Boceto31" plane through (0, 55, 0) normal (0, 1, 0) x (1, 0, 0) in component "Cuerpo"
  line L0 (-50.5, -62) -> (-48, -62)
  line L1 (-48, -62) -> (-48, -72)
  line L2 (-48, -72) -> (-50.5, -72)
  line L3 (-50.5, -72) -> (-50.5, -62)
extrude "Paso cable bateria (1)" cut sketch "Boceto31" along normal blind 7.4 bodies 1 in component "Cuerpo"
ref_plane "PlanoDeObra27" through (0, 36.9, 0) normal (0, 1, 0) x (0, 0, 1) in component "Cuerpo"
sketch "Boceto32" plane through (0, 36.9, 0) normal (0, 1, 0) x (1, 0, 0) in component "Cuerpo"
  circle A0 centre (-31, -48.7) radius 2.5
  circle A1 centre (32, -48.7) radius 2.5
  circle A2 centre (-31, -93.3) radius 2.5
  circle A3 centre (32, -93.3) radius 2.5
extrude "Insertos LiPo Rider (inserto 5x4) (1)" cut sketch "Boceto32" along normal blind 5 bodies 1 in component "Cuerpo"
ref_plane "PlanoDeObra28" through (0, 41.9, 0) normal (0, 1, 0) x (0, 0, 1) in component "Cuerpo"
sketch "Boceto33" plane through (0, 41.9, 0) normal (0, 1, 0) x (1, 0, 0) in component "Cuerpo"
  circle A0 centre (-31, -48.7) radius 1.6
  circle A1 centre (32, -48.7) radius 1.6
  circle A2 centre (-31, -93.3) radius 1.6
  circle A3 centre (32, -93.3) radius 1.6
extrude "Insertos LiPo Rider (paso M3) (1)" cut sketch "Boceto33" along normal blind 3 bodies 1 in component "Cuerpo"
ref_plane "PlanoDeObra29" through (0, 17.8, 0) normal (0, 1, 0) x (0, 0, 1) in component "Cuerpo"
ref_plane "PlanoDeObra30" through (0, 22.8, 0) normal (0, 1, 0) x (0, 0, 1) in component "Cuerpo"
ref_plane "PlanoDeObra31" through (0, 56, 0) normal (0, 1, 0) x (0, 0, 1) in component "Cuerpo"
sketch "Boceto36" plane through (0, 56, 0) normal (0, 1, 0) x (1, 0, 0) in component "Cuerpo"
  circle A0 centre (-19, -49.5) radius 2.5
  circle A1 centre (-19, -92.5) radius 2.5
extrude "Insertos traba (inserto 5x4) (1)" cut sketch "Boceto36" along normal blind 5 bodies 1 in component "Cuerpo"
ref_plane "PlanoDeObra32" through (0, 61, 0) normal (0, 1, 0) x (0, 0, 1) in component "Cuerpo"
sketch "Boceto37" plane through (0, 61, 0) normal (0, 1, 0) x (1, 0, 0) in component "Cuerpo"
  circle A0 centre (-19, -49.5) radius 1.6
  circle A1 centre (-19, -92.5) radius 1.6
extrude "Insertos traba (paso M3) (1)" cut sketch "Boceto37" along normal blind 3 bodies 1 in component "Cuerpo"
ref_plane "PlanoDeObra33" through (0, 35.9, 0) normal (0, 1, 0) x (0, 0, 1) in component "Cuerpo"
ref_plane "PlanoDeObra34" through (0, 38.4, 0) normal (0, 1, 0) x (0, 0, 1) in component "Cuerpo"
ref_plane "PlanoDeObra12" through (0, 0, 118) normal (0, 0, 1) x (1, 0, 0) in component "Techo solar"
sketch "Boceto16 (2)" plane through (0, 0, 118) normal (0, 0, 1) x (1, 0, 0) in component "Techo solar"
  circle A0 centre (42, 25.5) radius 1.5
extrude "Drenaje capsula (1)" cut sketch "Boceto16 (2)" along normal blind 13 bodies 5 in component "Techo solar"
sketch "Boceto17 (2)" plane through (0, 0, 0) normal (0, 0, 1) x (1, 0, 0) in component "Techo solar"
  point P0 (0, -22.9739)
  point P1 (10, -22.9739)
  point P2 (0, -13.577)
ref_plane "PlanoDeObra13" through (0, -22.9739, 101.1809) normal (0, -0.34202, 0.939693) x (1, 0, 0) in component "Techo solar"
sketch "Boceto18 (2)" plane through (0, -35.2064, 96.7287) normal (0, -0.34202, 0.939693) x (1, 0, 0) in component "Techo solar"
  line L0 (-55, 19.7175) -> (-39, 19.7175)
  line L1 (-39, 19.7175) -> (-39, 105.0175)
  line L2 (-39, 105.0175) -> (-55, 105.0175)
  line L3 (-55, 105.0175) -> (-55, 19.7175)
extrude "Refuerzo postes izquierdos (1)" add sketch "Boceto18 (2)" along normal blind 4.3 bodies 5 in component "Techo solar"
ref_plane "PlanoDeObra14" through (0, 0, 100) normal (0, 0, 1) x (1, 0, 0) in component "Techo solar"
sketch "Boceto19 (2)" plane through (0, 0, 100) normal (0, 0, 1) x (1, 0, 0) in component "Techo solar"
  circle A0 centre (-45, 18) radius 5
extrude "Poste techo izq y18 (1)" add sketch "Boceto19 (2)" along normal blind 18.3669 bodies 5 in component "Techo solar"
ref_plane "PlanoDeObra15" through (0, 0, 100) normal (0, 0, 1) x (1, 0, 0) in component "Techo solar"
sketch "Boceto20 (2)" plane through (0, 0, 100) normal (0, 0, 1) x (1, 0, 0) in component "Techo solar"
  circle A0 centre (45, 18) radius 5
extrude "Poste techo der y18 (1)" add sketch "Boceto20 (2)" along normal blind 21.4066 bodies 5 in component "Techo solar"
ref_plane "PlanoDeObra16" through (0, 0, 100) normal (0, 0, 1) x (1, 0, 0) in component "Techo solar"
sketch "Boceto21 (2)" plane through (0, 0, 100) normal (0, 0, 1) x (1, 0, 0) in component "Techo solar"
  circle A0 centre (-45, 52) radius 5
extrude "Poste techo izq y52 (1)" add sketch "Boceto21 (2)" along normal blind 30.7419 bodies 5 in component "Techo solar"
ref_plane "PlanoDeObra17" through (0, 0, 100) normal (0, 0, 1) x (1, 0, 0) in component "Techo solar"
sketch "Boceto22 (2)" plane through (0, 0, 100) normal (0, 0, 1) x (1, 0, 0) in component "Techo solar"
  circle A0 centre (45, 52) radius 5
extrude "Poste techo der y52 (1)" add sketch "Boceto22 (2)" along normal blind 33.7816 bodies 5 in component "Techo solar"
ref_plane "PlanoDeObra18" through (0, 0, 100) normal (0, 0, 1) x (1, 0, 0) in component "Techo solar"
sketch "Boceto23 (2)" plane through (0, 0, 100) normal (0, 0, 1) x (1, 0, 0) in component "Techo solar"
  circle A0 centre (-45, 18) radius 2.5
  circle A1 centre (45, 18) radius 2.5
  circle A2 centre (-45, 52) radius 2.5
  circle A3 centre (45, 52) radius 2.5
extrude "Insertos postes techo (inserto 5x4) (1)" cut sketch "Boceto23 (2)" along normal blind 5 bodies 5 in component "Techo solar"
ref_plane "PlanoDeObra19" through (0, 0, 105) normal (0, 0, 1) x (1, 0, 0) in component "Techo solar"
sketch "Boceto24 (2)" plane through (0, 0, 105) normal (0, 0, 1) x (1, 0, 0) in component "Techo solar"
  circle A0 centre (-45, 18) radius 1.6
  circle A1 centre (45, 18) radius 1.6
  circle A2 centre (-45, 52) radius 1.6
  circle A3 centre (45, 52) radius 1.6
extrude "Insertos postes techo (paso M3) (1)" cut sketch "Boceto24 (2)" along normal blind 3 bodies 5 in component "Techo solar"
ref_plane "PlanoDeObra20" through (0, 0, 101) normal (0, 0, 1) x (1, 0, 0) in component "Techo solar"
ref_plane "PlanoDeObra21" through (0, 0, 100) normal (0, 0, 1) x (1, 0, 0) in component "Techo solar"
sketch "Boceto26 (2)" plane through (0, 0, 100) normal (0, 0, 1) x (1, 0, 0) in component "Techo solar"
  line L0 (39, 30) -> (45, 30)
  line L1 (45, 30) -> (45, 44)
  line L2 (45, 44) -> (39, 44)
  line L3 (39, 44) -> (39, 30)
extrude "Paso cables sensor (1)'" cut sketch "Boceto26 (2)" along normal blind 35 bodies 5 in component "Techo solar"
ref_plane "PlanoDeObra22" through (0, 0, 125.6103) normal (0, 0, 1) x (1, 0, 0) in component "Techo solar"
sketch "Boceto27 (2)" plane through (0, 0, 125.6103) normal (0, 0, 1) x (1, 0, 0) in component "Techo solar"
  circle A0 centre (34.5, 30) radius 4
  circle A1 centre (49.5, 30) radius 4
extrude "Postes sensor y30 (1)" add sketch "Boceto27 (2)" along normal blind 20.2897 bodies 5 in component "Techo solar"
ref_plane "PlanoDeObra23" through (0, 0, 133.9816) normal (0, 0, 1) x (1, 0, 0) in component "Techo solar"
sketch "Boceto28" plane through (0, 0, 133.9816) normal (0, 0, 1) x (1, 0, 0) in component "Techo solar"
  circle A0 centre (34.5, 53) radius 4
  circle A1 centre (49.5, 53) radius 4
extrude "Postes sensor y53 (1)" add sketch "Boceto28" along normal blind 11.9184 bodies 5 in component "Techo solar"
ref_plane "PlanoDeObra24" through (0, 0, 145.9) normal (0, 0, 1) x (1, 0, 0) in component "Techo solar"
sketch "Boceto29 (2)" plane through (0, 0, 145.9) normal (0, 0, 1) x (1, 0, 0) in component "Techo solar"
  circle A0 centre (34.5, 30) radius 2.5
  circle A1 centre (49.5, 30) radius 2.5
  circle A2 centre (34.5, 53) radius 2.5
  circle A3 centre (49.5, 53) radius 2.5
extrude "Insertos sensor (inserto 5x4) (1)" cut sketch "Boceto29 (2)" against normal blind 5 bodies 5 in component "Techo solar"
ref_plane "PlanoDeObra25" through (0, 0, 140.9) normal (0, 0, 1) x (1, 0, 0) in component "Techo solar"
sketch "Boceto30 (2)" plane through (0, 0, 140.9) normal (0, 0, 1) x (1, 0, 0) in component "Techo solar"
  circle A0 centre (34.5, 30) radius 1.6
  circle A1 centre (49.5, 30) radius 1.6
  circle A2 centre (34.5, 53) radius 1.6
  circle A3 centre (49.5, 53) radius 1.6
extrude "Insertos sensor (paso M3) (1)" cut sketch "Boceto30 (2)" against normal blind 3 bodies 5 in component "Techo solar"
ref_plane "PlanoDeObra26" through (0, 40, 0) normal (0, 1, 0) x (0, 0, 1) in component "Techo solar"
sketch "Boceto31 (2)" plane through (0, 40, 0) normal (0, 1, 0) x (1, 0, 0) in component "Techo solar"
  line L0 (29.4, -147.8) -> (30, -147.8)
  line L1 (30, -147.8) -> (30, -149.2)
  line L2 (30, -149.2) -> (29.4, -149.2)
  line L3 (29.4, -149.2) -> (29.4, -147.8)
  line L4 (54, -147.8) -> (54.6, -147.8)
  line L5 (54.6, -147.8) -> (54.6, -149.2)
  line L6 (54.6, -149.2) -> (54, -149.2)
  line L7 (54, -149.2) -> (54, -147.8)
extrude "Ranuras enganche tapa sensor (1)" cut sketch "Boceto31 (2)" along normal blind 10 bodies 5 in component "Techo solar"
ref_plane "PlanoDeObra8" through (0, 41, 0) normal (0, 1, 0) x (0, 0, 1) in component "Tapa sensor"
sketch "Boceto8" plane through (0, 41, 0) normal (0, 1, 0) x (1, 0, 0) in component "Tapa sensor"
  line L0 (29.8, -148) -> (30.5, -148)
  line L1 (30.5, -148) -> (30.5, -149)
  line L2 (30.5, -149) -> (29.8, -149)
  line L3 (29.8, -149) -> (29.8, -148)
  line L4 (53.5, -148) -> (54.2, -148)
  line L5 (54.2, -148) -> (54.2, -149)
  line L6 (54.2, -149) -> (53.5, -149)
  line L7 (53.5, -149) -> (53.5, -148)
extrude "Enganches tapa sensor (1)" add sketch "Boceto8" along normal blind 8 bodies 6 in component "Tapa sensor"
ref_plane "PlanoDeObra13" through (0, -2.5, 0) normal (0, 1, 0) x (0, 0, 1) in component "Tapa frontal"
ref_plane "PlanoDeObra14" through (0, 6.5, 0) normal (0, 1, 0) x (0, 0, 1) in component "Tapa frontal"
ref_plane "PlanoDeObra15" through (0, 1.5, 0) normal (0, 1, 0) x (0, 0, 1) in component "Tapa frontal"
ref_plane "PlanoDeObra16" through (0, -5, 0) normal (0, 1, 0) x (0, 0, 1) in component "Tapa frontal"
ref_plane "PlanoDeObra17" through (0, -5, 0) normal (0, 1, 0) x (0, 0, 1) in component "Tapa frontal"
ref_plane "PlanoDeObra18" through (0, -2.5, 0) normal (0, 1, 0) x (0, 0, 1) in component "Tapa frontal"
sketch "Boceto18 (3)" plane through (0, -2.5, 0) normal (0, 1, 0) x (1, 0, 0) in component "Tapa frontal"
  circle A0 centre (-7.75, -38.5) radius 3
  circle A1 centre (7.75, -38.5) radius 3
extrude "Postes semaforo d6 (1)" add sketch "Boceto18 (3)" along normal blind 9 bodies 2 in component "Tapa frontal"
ref_plane "PlanoDeObra19" through (0, -6, 0) normal (0, 1, 0) x (0, 0, 1) in component "Tapa frontal"
ref_plane "PlanoDeObra20" through (0, -5, 0) normal (0, 1, 0) x (0, 0, 1) in component "Tapa frontal"
sketch "Boceto32 (2)" plane through (0, 0, 0) normal (0, 0, 1) x (1, 0, 0) in component "Techo solar"
  point P0 (0, -25.351)
  point P1 (10, -25.351)
  point P2 (0, -15.9541)
ref_plane "PlanoDeObra27" through (0, -25.351, 107.7118) normal (0, -0.34202, 0.939693) x (1, 0, 0) in component "Techo solar"
sketch "Boceto33 (2)" plane through (0, -37.5834, 103.2595) normal (0, -0.34202, 0.939693) x (1, 0, 0) in component "Techo solar"
  line L0 (-41, 116.0175) -> (11, 116.0175)
  line L1 (11, 116.0175) -> (11, 121.0175)
  line L2 (11, 121.0175) -> (-41, 121.0175)
  line L3 (-41, 121.0175) -> (-41, 116.0175)
extrude "Quitar pestanas traseras (1)" cut sketch "Boceto33 (2)" along normal blind 2.05 bodies 5 in component "Techo solar"
sketch "Boceto34" plane through (0, 0, 0) normal (0, 0, 1) x (1, 0, 0) in component "Techo solar"
  point P0 (0, -24.4788)
  point P1 (10, -24.4788)
  point P2 (0, -15.0819)
ref_plane "PlanoDeObra28" through (0, -24.4788, 105.3156) normal (0, -0.34202, 0.939693) x (1, 0, 0) in component "Techo solar"
sketch "Boceto35" plane through (0, -36.7113, 100.8633) normal (0, -0.34202, 0.939693) x (1, 0, 0) in component "Techo solar"
  line L0 (-55, 118.0175) -> (25.6, 118.0175)
  line L1 (25.6, 118.0175) -> (25.6, 127.0175)
  line L2 (25.6, 127.0175) -> (-55, 127.0175)
  line L3 (-55, 127.0175) -> (-55, 118.0175)
extrude "Entrada panel (1)" cut sketch "Boceto35" along normal blind 2.9 bodies 5 in component "Techo solar"
sketch "Boceto36 (2)" plane through (0, 0, 0) normal (0, 0, 1) x (1, 0, 0) in component "Techo solar"
  point P0 (0, -22.9739)
  point P1 (10, -22.9739)
  point P2 (0, -13.577)
ref_plane "PlanoDeObra29" through (0, -22.9739, 101.1809) normal (0, -0.34202, 0.939693) x (1, 0, 0) in component "Techo solar"
sketch "Boceto38" plane through (0, 0, 0) normal (0, 0, 1) x (1, 0, 0) in component "Techo solar"
  point P0 (0, -21.4158)
  point P1 (10, -21.4158)
  point P2 (0, -24.836)
ref_plane "PlanoDeObra30" through (0, -21.4158, 104.9406) normal (0, -0.939693, -0.34202) x (1, 0, 0) in component "Techo solar"